Autodesk Fusion 360 part; units mm, degrees
(part 2 of 2)
equation "case_top_inner_border_top_fillet_Ref_Ref = 1 mm"
equation "usbc_contour_height_Ref_Ref = 4.5 mm"
equation "usbc_contour_length_Ref_Ref = 12 mm"
equation "assemblyscr_head_diameter_Ref_Ref = 4.15 mm"
equation "assemblyscr_head_width_Ref_Ref = 0.85 mm"
equation "rf_diameter_Ref_Ref = 10 mm"
equation "rf_width_Ref_Ref = 0.5 mm"
equation "rf_voffset_Ref_Ref = case_border_width_Ref_Ref + 10 mm"
equation "rf_hoffset_Ref_Ref = case_border_width_Ref_Ref + 15 mm"
equation "ctrl_extension_width_Ref = 7.885 mm"
equation "pcase_max_length_Ref = sw_size_Ref_Ref * 8 + ( plt_border_width_Ref_Ref + case_border_width_Ref_Ref ) * 2 + ctrl_extension_width_Ref"
equation "pcase_bot_max_thickness_Ref = pcase_max_length_Ref / tan(90 deg - case_bot_angle_Ref_Ref) + case_bot_min_thickness_Ref_Ref"
equation "d69 = sw_size_Ref_Ref * 6"
equation "d70 = sw_size_Ref_Ref * 2"
equation "d71 = col_mid_offset_Ref_Ref"
equation "d72 = sw_size_Ref_Ref"
equation "d73 = col_ring_offset_Ref_Ref"
equation "d74 = sw_size_Ref_Ref"
equation "d75 = col_pinky_offset_Ref_Ref"
equation "d76 = sw_size_Ref_Ref * 3"
equation "d77 = col_ring_offset_Ref_Ref - col_mid_offset_Ref_Ref"
equation "d78 = sw_size_Ref_Ref"
equation "d79 = col_pinky_offset_Ref_Ref"
equation "d80 = sw_size_Ref_Ref * 3"
equation "d81 = sw_size_Ref_Ref"
equation "d84 = ( sw_size_Ref_Ref - 18 mm ) * 0.5"
equation "d85 = ( sw_size_Ref_Ref - 18 mm ) * 0.5"
equation "d86 = sw_size_Ref_Ref"
equation "d87 = sw_size_Ref_Ref"
equation "d88 = sw_size_Ref_Ref * 2"
equation "d89 = sw_size_Ref_Ref * 2"
equation "d90 = sw_size_Ref_Ref * 3"
equation "d91 = ctrl_extension_width_Ref + plt_border_width_Ref_Ref"
equation "d92 = plt_border_width_Ref_Ref"
equation "d93 = ctrl_extension_width_Ref + plt_border_width_Ref_Ref"
equation "d94 = plt_border_width_Ref_Ref"
equation "d95 = plt_border_width_Ref_Ref"
equation "d96 = ctrl_extension_width_Ref + plt_border_width_Ref_Ref"
equation "d97 = plt_border_width_Ref_Ref"
equation "d98 = ctrl_extension_width_Ref + plt_border_width_Ref_Ref"
equation "d99 = plt_border_width_Ref_Ref"
equation "d100 = plt_border_width_Ref_Ref"
equation "d101 = plt_border_width_Ref_Ref"
equation "d102 = plt_border_width_Ref_Ref"
equation "d103 = plt_border_width_Ref_Ref"
equation "d104 = plt_border_width_Ref_Ref"
equation "d105 = plt_border_width_Ref_Ref"
equation "d106 = plt_border_width_Ref_Ref"
equation "d107 = plt_border_width_Ref_Ref"
equation "d108 = plt_border_width_Ref_Ref"
equation "d109 = plt_border_width_Ref_Ref"
equation "d110 = plt_border_width_Ref_Ref"
equation "d111 = plt_border_width_Ref_Ref"
equation "d112 = plt_border_width_Ref_Ref"
equation "d113 = plt_border_width_Ref_Ref"
equation "d114 = plt_border_width_Ref_Ref"
equation "d115 = plt_border_width_Ref_Ref"
equation "d116 = plt_border_width_Ref_Ref"
equation "d117 = plt_border_width_Ref_Ref"
equation "d118 = plt_border_width_Ref_Ref"
equation "d119 = plt_border_width_Ref_Ref"
equation "d120 = plt_border_width_Ref_Ref"
equation "d121 = plt_border_width_Ref_Ref"
equation "d122 = plt_border_width_Ref_Ref"
equation "d123 = case_border_width_Ref_Ref"
equation "d124 = -plt_border_width_Ref_Ref"
equation "d125 = -( case_bot_max_thickness_Ref_Ref + pcb_thickness_Ref_Ref + pcb_clearance_Ref_Ref + plt_thickness_Ref_Ref + ( plt_up_clearance_Ref_Ref - case_top_thickness_Ref_Ref ) )"
equation "d127 = -( plt_up_clearance_Ref_Ref - case_top_thickness_Ref_Ref + plt_thickness_Ref_Ref + pcb_thickness_Ref_Ref + 0.05 mm )"
equation "d129 = top_align_mark_length_Ref_Ref"
equation "d130 = top_align_mark_length_Ref_Ref"
equation "d131 = top_align_mark_length_Ref_Ref"
equation "d132 = top_align_mark_length_Ref_Ref"
equation "d133 = top_align_mark_length_Ref_Ref"
equation "d134 = top_align_mark_length_Ref_Ref"
equation "d136 = alignh_diameter_Ref_Ref + 0.05 mm"
equation "d137 = alignh_diameter_Ref_Ref + 0.05 mm"
equation "d139 = alignh_diameter_Ref_Ref + 0.05 mm"
equation "d140 = alignh_diameter_Ref_Ref + 0.05 mm"
equation "d141 = alignh_diameter_Ref_Ref + 0.05 mm"
equation "d143 = alignh_diameter_Ref_Ref + 0.05 mm"
equation "d144 = alignh_diameter_Ref_Ref + 0.05 mm"
equation "d145 = alignh_diameter_Ref_Ref + 0.05 mm"
equation "d146 = alignh_diameter_Ref_Ref + 0.05 mm"
equation "d147 = case_border_width_Ref_Ref * 1.75"
equation "d148 = case_border_width_Ref_Ref * 1.75"
equation "d149 = case_border_width_Ref_Ref * 1.75"
equation "d150 = case_border_width_Ref_Ref * 1.25"
equation "d151 = m2scr_diameter_Ref_Ref"
equation "d152 = m2scr_diameter_Ref_Ref"
equation "d153 = m2scr_diameter_Ref_Ref"
equation "d154 = m2scr_diameter_Ref_Ref"
equation "d155 = -alignh_height_Ref_Ref + 0.05 mm"
equation "d158 = ( alignh_diameter_Ref_Ref + 0.05 mm ) * 0.5"
equation "d160 = -( plt_up_clearance_Ref_Ref - case_top_thickness_Ref_Ref + plt_thickness_Ref_Ref + pcb_thickness_Ref_Ref * 0.5 )"
equation "d162 = sw_size_Ref_Ref * 5 + ctrl_height_Ref_Ref * 0.5"
equation "d163 = ctrl_socket_height_Ref_Ref - usbc_height_Ref_Ref * 0.5"
equation "d164 = usbc_length_Ref_Ref"
equation "d165 = usbc_height_Ref_Ref"
equation "d166 = usbc_contour_length_Ref_Ref"
equation "d167 = usbc_contour_height_Ref_Ref"
equation "d168 = bat_offset_Ref_Ref - bat_length_Ref_Ref * 0.5 - bat_wall_thickness_Ref_Ref"
equation "d175 = bat_wall_thickness_Ref_Ref"
equation "d177 = bat_wall_thickness_Ref_Ref * 2 + bat_height_Ref_Ref"
equation "d179 = -bat_wall_thickness_Ref_Ref * 0.5"
equation "d181 = -bat_wall_thickness_Ref_Ref * 0.5"
equation "d187 = ( ctrl_height_Ref_Ref + 0.5 mm ) * 0.5"
equation "d188 = ctrl_height_Ref_Ref + 0.5 mm"
equation "d189 = ctrl_width_Ref_Ref + ctrl_socket_height_Ref_Ref + 0.5 mm"
equation "d190 = -plt_border_width_Ref_Ref"
equation "d192 = sw_size_Ref_Ref * 5.5"
equation "d196 = ( ( 6.8 + 1 ) * 0.5 ) * 1 mm"
equation "d197 = ( ( 6.8 + 1 ) * 0.5 ) * 1 mm"
equation "d200 = -1.4 mm - 0.25 mm"
equation "d206 = top_align_mark_length_Ref_Ref"
equation "d207 = top_align_mark_length_Ref_Ref"
equation "d208 = top_align_mark_length_Ref_Ref"
equation "d209 = top_align_mark_length_Ref_Ref"
equation "d210 = -case_bot_angle_Ref_Ref"
equation "d212 = -case_bot_max_thickness_Ref_Ref"
equation "d214 = top_align_mark_length_Ref_Ref"
equation "d215 = alignh_diameter_Ref_Ref + 0.05 mm"
equation "d216 = alignh_diameter_Ref_Ref + 0.05 mm"
equation "d217 = alignh_diameter_Ref_Ref + 0.05 mm"
equation "d219 = alignh_diameter_Ref_Ref + 0.05 mm"
equation "d221 = alignh_diameter_Ref_Ref + 0.05 mm"
equation "d222 = -alignh_height_Ref_Ref - 0.05 mm"
equation "d225 = ( alignh_diameter_Ref_Ref + 0.05 mm ) * 0.5"
equation "d227 = case_side_fillet_Ref_Ref"
equation "d230 = sw_hotswap_clearance_Ref_Ref"
equation "d231 = bat_wall_thickness_Ref_Ref"
equation "d232 = bat_width_Ref_Ref + bat_wall_thickness_Ref_Ref"
equation "d233 = bat_length_Ref_Ref + 0.5 mm"
equation "d234 = bat_width_Ref_Ref"
equation "d235 = bat_wall_thickness_Ref_Ref"
equation "d236 = bat_width_Ref_Ref + bat_wall_thickness_Ref_Ref"
